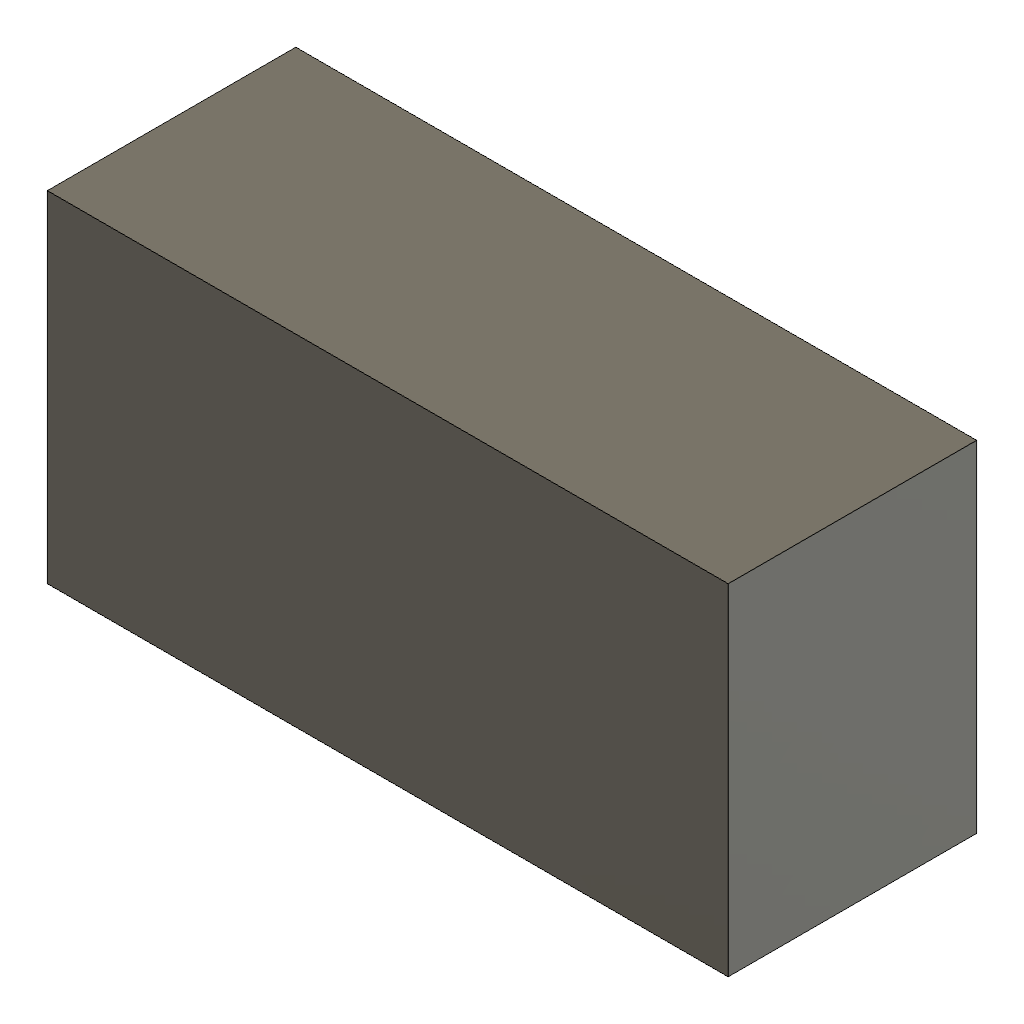
model_favorite_true (Autodesk Fusion 360 design; units mm, degrees)
part number: 2026-10-20-22-27-42-551
Autodesk Fusion 360 part; units mm, degrees
sketch "Sketch1" plane through (0, 0, 0) normal (0, 0, 1) x (1, 0, 0)
  line L0 (0, 0) -> (20, 0)
  line L1 (20, 0) -> (20, 10)
  line L2 (20, 10) -> (0, 10)
  line L3 (0, 10) -> (0, 0)
extrude "ProbeExtrude" add sketch "Sketch1" along normal blind 7.3
